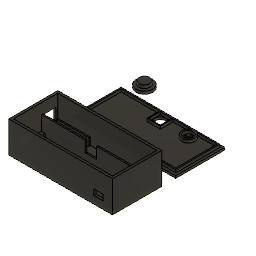
pulsador render (Autodesk Fusion 360 design; units mm, degrees)
part number: 2026-10-25-22-18-41-954
Autodesk Fusion 360 part; units mm, degrees
sketch "Boceto1" plane through (0, 0, 0) normal (0, 0, 1) x (1, 0, 0)
  line L0 (0, 0) -> (111, 0)
  line L1 (111, 0) -> (111, 52.6)
  line L2 (111, 52.6) -> (0, 52.6)
  line L3 (0, 52.6) -> (0, 0)
extrude "Extruir1" add sketch "Boceto1" along normal blind 33.5 makes body 1
ref_plane "PlanoDeObra1" through (0, 0, 2.5) normal (0, 0, 1) x (1, 0, 0)
sketch "Boceto2" plane through (0, 0, 2.5) normal (0, 0, 1) x (1, 0, 0)
  line L0 (2.5, 2.5) -> (108.5, 2.5)
  line L1 (108.5, 2.5) -> (108.5, 50.1)
  line L2 (108.5, 50.1) -> (2.5, 50.1)
  line L3 (2.5, 50.1) -> (2.5, 2.5)
extrude "Extruir2" cut sketch "Boceto2" along normal blind 32 bodies 1
ref_plane "PlanoDeObra2" through (0, 0, 2) normal (0, 0, 1) x (1, 0, 0)
sketch "Boceto3" plane through (0, 0, 2) normal (0, 0, 1) x (1, 0, 0)
  line L0 (2.5, 32.5) -> (108.5, 32.5)
  line L1 (108.5, 32.5) -> (108.5, 34.1)
  line L2 (108.5, 34.1) -> (2.5, 34.1)
  line L3 (2.5, 34.1) -> (2.5, 32.5)
extrude "Extruir3" add sketch "Boceto3" along normal blind 20.5 bodies 1
ref_plane "PlanoDeObra3" through (0, 0, 10.5) normal (0, 0, 1) x (1, 0, 0)
sketch "Boceto4" plane through (0, 0, 10.5) normal (0, 0, 1) x (1, 0, 0)
  line L0 (49.5, 32) -> (61.5, 32)
  line L1 (61.5, 32) -> (61.5, 34.6)
  line L2 (61.5, 34.6) -> (49.5, 34.6)
  line L3 (49.5, 34.6) -> (49.5, 32)
extrude "Extruir4" cut sketch "Boceto4" along normal blind 13 bodies 1
sketch "Boceto5" plane through (0, 0, 2) normal (0, 0, 1) x (1, 0, 0)
  line L0 (3, 3) -> (7, 3)
  line L1 (7, 3) -> (7, 7)
  line L2 (7, 7) -> (3, 7)
  line L3 (3, 7) -> (3, 3)
extrude "Extruir5" add sketch "Boceto5" along normal blind 5.5 bodies 1
sketch "Boceto6" plane through (0, 0, 2) normal (0, 0, 1) x (1, 0, 0)
  line L0 (3, 28) -> (7, 28)
  line L1 (7, 28) -> (7, 32)
  line L2 (7, 32) -> (3, 32)
  line L3 (3, 32) -> (3, 28)
extrude "Extruir6" add sketch "Boceto6" along normal blind 5.5 bodies 1
sketch "Boceto7" plane through (0, 0, 2) normal (0, 0, 1) x (1, 0, 0)
  line L0 (104, 3) -> (108, 3)
  line L1 (108, 3) -> (108, 7)
  line L2 (108, 7) -> (104, 7)
  line L3 (104, 7) -> (104, 3)
extrude "Extruir7" add sketch "Boceto7" along normal blind 5.5 bodies 1
sketch "Boceto8" plane through (0, 0, 2) normal (0, 0, 1) x (1, 0, 0)
  line L0 (104, 28) -> (108, 28)
  line L1 (108, 28) -> (108, 32)
  line L2 (108, 32) -> (104, 32)
  line L3 (104, 32) -> (104, 28)
extrude "Extruir8" add sketch "Boceto8" along normal blind 5.5 bodies 1
sketch "Boceto9" plane through (0, 0, 2) normal (0, 0, 1) x (1, 0, 0)
  line L0 (3, 34.4) -> (37.5, 34.4)
  line L1 (37.5, 34.4) -> (37.5, 35.9)
  line L2 (37.5, 35.9) -> (3, 35.9)
  line L3 (3, 35.9) -> (3, 34.4)
extrude "Extruir9" add sketch "Boceto9" along normal blind 8.5 bodies 1
sketch "Boceto10" plane through (0, 0, 2) normal (0, 0, 1) x (1, 0, 0)
  line L0 (3, 48.3) -> (37.5, 48.3)
  line L1 (37.5, 48.3) -> (37.5, 49.8)
  line L2 (37.5, 49.8) -> (3, 49.8)
  line L3 (3, 49.8) -> (3, 48.3)
extrude "Extruir10" add sketch "Boceto10" along normal blind 8.5 bodies 1
ref_plane "PlanoDeObra4" through (0, 0, 3) normal (0, 0, 1) x (1, 0, 0)
sketch "Boceto11" plane through (0, 0, 3) normal (0, 0, 1) x (1, 0, 0)
  line L0 (-1, 10.5) -> (3, 10.5)
  line L1 (3, 10.5) -> (3, 24.5)
  line L2 (3, 24.5) -> (-1, 24.5)
  line L3 (-1, 24.5) -> (-1, 10.5)
extrude "Extruir11" cut sketch "Boceto11" along normal blind 9 bodies 1
ref_plane "PlanoDeObra5" through (0, 0, 9.5) normal (0, 0, 1) x (1, 0, 0)
sketch "Boceto12" plane through (0, 0, 9.5) normal (0, 0, 1) x (1, 0, 0)
  line L0 (-1, 36.1) -> (3, 36.1)
  line L1 (3, 36.1) -> (3, 48.1)
  line L2 (3, 48.1) -> (-1, 48.1)
  line L3 (-1, 48.1) -> (-1, 36.1)
extrude "Extruir12" cut sketch "Boceto12" along normal blind 12 bodies 1
ref_plane "PlanoDeObra6" through (0, 0, 8.1) normal (0, 0, 1) x (1, 0, 0)
sketch "Boceto13" plane through (0, 0, 8.1) normal (0, 0, 1) x (1, 0, 0)
  line L0 (91, -1) -> (101, -1)
  line L1 (101, -1) -> (101, 3)
  line L2 (101, 3) -> (91, 3)
  line L3 (91, 3) -> (91, -1)
extrude "Extruir13" cut sketch "Boceto13" along normal blind 6 bodies 1
sketch "Boceto14" plane through (0, 0, 0) normal (0, 0, 1) x (1, 0, 0)
  line L0 (0, 67.6) -> (111, 67.6)
  line L1 (111, 67.6) -> (111, 120.2)
  line L2 (111, 120.2) -> (0, 120.2)
  line L3 (0, 120.2) -> (0, 67.6)
extrude "Extruir14" add sketch "Boceto14" along normal blind 2.5 separate body makes body 2
sketch "Boceto15" plane through (0, 0, 2) normal (0, 0, 1) x (1, 0, 0)
  line L0 (2.65, 70.25) -> (108.35, 70.25)
  line L1 (108.35, 70.25) -> (108.35, 117.55)
  line L2 (108.35, 117.55) -> (2.65, 117.55)
  line L3 (2.65, 117.55) -> (2.65, 70.25)
extrude "Extruir15" add sketch "Boceto15" along normal blind 3.5 bodies 2
sketch "Boceto16" plane through (0, 0, 2.5) normal (0, 0, 1) x (1, 0, 0)
  line L0 (4.15, 71.75) -> (106.85, 71.75)
  line L1 (106.85, 71.75) -> (106.85, 116.05)
  line L2 (106.85, 116.05) -> (4.15, 116.05)
  line L3 (4.15, 116.05) -> (4.15, 71.75)
extrude "Extruir16" cut sketch "Boceto16" along normal blind 4 bodies 2
sketch "Boceto17" plane through (0, 0, 2) normal (0, 0, 1) x (1, 0, 0)
  line L0 (45.3, 102.5) -> (59.7, 102.5)
  line L1 (59.7, 102.5) -> (59.7, 116.9)
  line L2 (59.7, 116.9) -> (45.3, 116.9)
  line L3 (45.3, 116.9) -> (45.3, 102.5)
extrude "Extruir17" add sketch "Boceto17" along normal blind 3.5 bodies 2
sketch "Boceto18" plane through (0, 0, 2.5) normal (0, 0, 1) x (1, 0, 0)
  line L0 (46.3, 103.5) -> (58.7, 103.5)
  line L1 (58.7, 103.5) -> (58.7, 115.9)
  line L2 (58.7, 115.9) -> (46.3, 115.9)
  line L3 (46.3, 115.9) -> (46.3, 103.5)
extrude "Extruir18" cut sketch "Boceto18" along normal blind 4 bodies 2
sketch "Boceto19" plane through (0, 0, 2) normal (0, 0, 1) x (1, 0, 0)
  circle A0 centre (82.5, 109.7) radius 7
extrude "Extruir19" add sketch "Boceto19" along normal blind 3.5 bodies 2
sketch "Boceto20" plane through (0, 0, 2.5) normal (0, 0, 1) x (1, 0, 0)
  circle A0 centre (82.5, 109.7) radius 5.2
extrude "Extruir20" cut sketch "Boceto20" along normal blind 4 bodies 2
ref_plane "PlanoDeObra7" through (0, 0, -1) normal (0, 0, 1) x (1, 0, 0)
sketch "Boceto21" plane through (0, 0, -1) normal (0, 0, 1) x (1, 0, 0)
  circle A0 centre (52.5, 109.7) radius 5.95
extrude "Extruir21" cut sketch "Boceto21" along normal blind 4.5 bodies 2
sketch "Boceto22" plane through (0, 0, -1) normal (0, 0, 1) x (1, 0, 0)
  circle A0 centre (82.5, 109.7) radius 1.25
extrude "Extruir22" cut sketch "Boceto22" along normal blind 4.5 bodies 2
sketch "Boceto23" plane through (0, 0, -1) normal (0, 0, 1) x (1, 0, 0)
  circle A0 centre (85.5, 109.7) radius 1.25
extrude "Extruir23" cut sketch "Boceto23" along normal blind 4.5 bodies 2
sketch "Boceto24" plane through (0, 0, -1) normal (0, 0, 1) x (1, 0, 0)
  circle A0 centre (79.5, 109.7) radius 1.25
extrude "Extruir24" cut sketch "Boceto24" along normal blind 4.5 bodies 2
sketch "Boceto25" plane through (0, 0, -1) normal (0, 0, 1) x (1, 0, 0)
  circle A0 centre (82.5, 112.7) radius 1.25
extrude "Extruir25" cut sketch "Boceto25" along normal blind 4.5 bodies 2
sketch "Boceto26" plane through (0, 0, -1) normal (0, 0, 1) x (1, 0, 0)
  circle A0 centre (82.5, 106.7) radius 1.25
extrude "Extruir26" cut sketch "Boceto26" along normal blind 4.5 bodies 2
sketch "Boceto27" plane through (0, 0, 0) normal (0, 0, 1) x (1, 0, 0)
  circle A0 centre (10, 135.2) radius 9
extrude "Extruir27" add sketch "Boceto27" along normal blind 3 separate body makes body 3
sketch "Boceto28" plane through (0, 0, 2.5) normal (0, 0, 1) x (1, 0, 0)
  circle A0 centre (10, 135.2) radius 5.75
extrude "Extruir28" add sketch "Boceto28" along normal blind 4 bodies 3
named bodies: "Base", "Tapa", "Pulsador"
